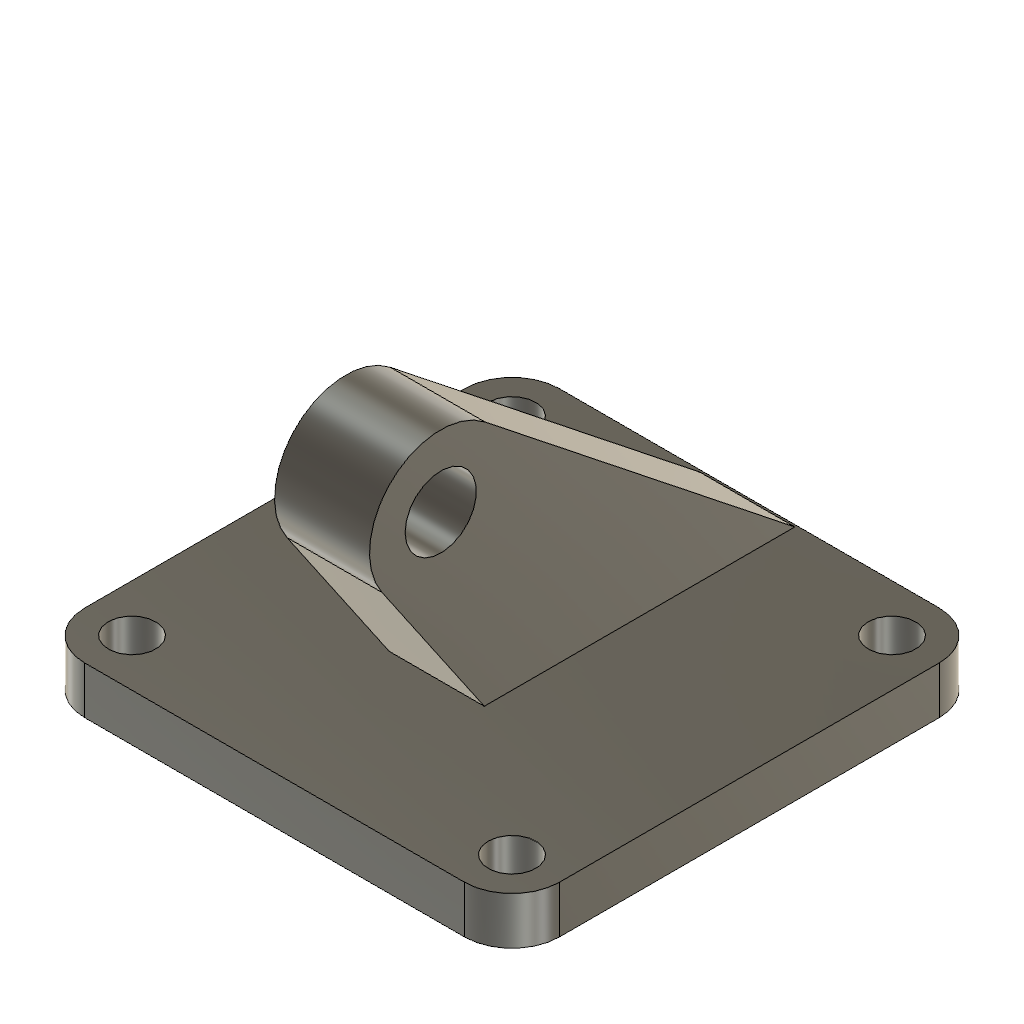
generative (Autodesk Fusion 360 design; units mm, degrees)
part number: 2026-10-01-13-19-30-710
Autodesk Fusion 360 part; units mm, degrees
sketch "Sketch1" plane through (0, 0, 0) normal (0, 0, 1) x (1, 0, 0)
  line L0 (100, -100) -> (-100, -100)
  line L1 (-100, -100) -> (-100, 100)
  line L2 (-100, 100) -> (100, 100)
  line L3 (100, 100) -> (100, -100)
  line L4 (100, -100) -> (-100, 100) construction
  line L5 (-100, -100) -> (100, 100) construction
  line L6 (80, -80) -> (-80, -80)
  line L7 (-80, -80) -> (-80, 80)
  line L8 (-80, 80) -> (80, 80)
  line L9 (80, 80) -> (80, -80)
  line L10 (80, -80) -> (-80, 80) construction
  line L11 (-80, -80) -> (80, 80) construction
  circle A0 centre (80, 80) radius 10
  circle A1 centre (-80, 80) radius 10
  circle A2 centre (-80, -80) radius 10
  circle A3 centre (80, -80) radius 10
  dimension "d1" = 200
  dimension "d2" = 200
  dimension "d3" = 160
  dimension "d4" = 160
  dimension "d5" = 20
  dimension "d6" = 20
  dimension "d7" = 20
  dimension "d8" = 20
  constraint horizontal L0
  constraint perpendicular L0 L1
  constraint parallel L0 L2
  constraint parallel L1 L3
  constraint coincident L4 origin
  constraint coincident L5 origin
  constraint horizontal L6
  constraint perpendicular L6 L7
  constraint parallel L6 L8
  constraint parallel L7 L9
  constraint coincident L10 origin
  constraint coincident L11 origin
  constraint coincident L8.end L9.start
  constraint coincident L7.end L8.start
  constraint coincident L6.end L7.start
  constraint coincident L6.start L9.end
  measures "d1" distance of L1.end L2.end
  measures "d2" distance of L0.end L1.end
  measures "d3" distance of L7.end L8.end
  measures "d4" distance of L6.end L7.end
  measures "d5" diameter of A0
  measures "d6" diameter of A1
  measures "d7" diameter of A2
  measures "d8" diameter of A3
extrude "Extrude1" add sketch "Sketch1" along normal blind 20 contours L0 L1 L2 L3 | L6 L7 L8 L9 A0 A1 A2 A3
fillet "Fillet1" radius 20 4 edges at (100, -100, 10) (-100, -100, 10) (100, 100, 10) (-100, 100, 10)
sketch "Sketch2" plane through (100, 0, 0) normal (1, 0, 0) x (0, 1, 0)
  line L0 (80, 0) -> (80, 20)
  line L1 (80, 20) -> (-80, 20)
  line L2 (-80, 20) -> (-80, 0)
  line L3 (-80, 0) -> (80, 0)
  line L4 (100, 0) -> (-50, 0)
  line L5 (-50, 0) -> (-50, 100)
  line L6 (-50, 100) -> (100, 100)
  line L7 (100, 100) -> (100, 0)
  circle A0 centre (-50, 100) radius 15
  circle A1 centre (-50, 100) radius 30
  line L8 (100, 0) -> (-18, 0)
  line L9 (-74.7691, 83.0739) -> (-18, 0)
  line L10 (-31.3533, 123.5011) -> (100, 19.28)
  line L11 (80, 20) -> (100, 20)
  dimension "d13" = 150
  dimension "d14" = 100
  dimension "d15" = 30
  dimension "d16" = 60
  dimension "d17" = 118
  constraint horizontal L4
  constraint vertical L5
  constraint horizontal L6
  constraint vertical L7
  constraint coincident L5.end L6.start
  constraint concentric A0 A1
  constraint perpendicular L7 L8
  constraint coincident A1 L9.start
  constraint coincident A1 L10.start
  constraint coincident L7 L10.end
  constraint tangent A1 L9
  constraint tangent A1 L10
  constraint coincident L0.end L1.start
  constraint coincident L7 L11.end
  constraint perpendicular L7 L11
  measures "d13" distance of L4.start L4.end
  measures "d14" distance of L4.start L6.end
  measures "d15" diameter of A0
  measures "d16" diameter of A1
  measures "d17" distance of L4.start L8.end
extrude "Extrude2" add sketch "Sketch2" along normal blind -80 and the other way blind 120 contours L1 L5 L6 A1 L9 L10 L11 | L5 A1 L9 | L6 A1 L10 | L5 L6 A0 A1 | L5 L6 A0 A1
